Push_rod_pin_v2 (Autodesk Fusion 360 design; units mm, degrees)
Autodesk Fusion 360 part; units mm, degrees
sketch "sketch 384" plane through (0, 0, 0) normal (-1, 0, 0) x (0, -1, 0)
  circle A0 centre (0, 0) radius 4
  circle A1 centre (0, 0) radius 4
extrude "Extrude1" add sketch "sketch 384" against normal blind 17.6
chamfer "Chamfer1" distance 1 angle 45 2 edges at (17.6, 3.7293, 1.4465) (0, 3.7293, -1.4465) tangent chain off
